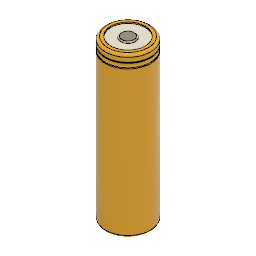
Desktop Assembly (Autodesk Fusion 360 archive; units mm, degrees)
design "18650 Battery"
Autodesk Fusion 360 part; units mm, degrees
sketch "Sketch1" plane through (0, 0, 0) normal (0, 0, 1) x (1, 0, 0)
  line L0 (0, 0) -> (0, 64.9)
  line L1 (0, 64.9) -> (9.215, 64.9)
  line L2 (9.215, 0) -> (0, 0)
  line L3 (9.215, 64.9) -> (9.215, 61.9)
  arc A0 (9.215, 61.9) -> (9.215, 60.0196) centre (10.9802, 60.9598) ccw
  line L4 (9.215, 60.0196) -> (9.215, 0)
  dimension "d1" = 9.215
  dimension "d2" = 64.9
  dimension "d5" = 2
  dimension "d6" = 3
  measures "d1" distance of L0.start
  measures "d5" radius of A0
revolve "Revolve1" add sketch "Sketch1" angle 360 about axis through (0, 0, 0) along (0, 1, 0)
fillet "Fillet1" radius 1 2 edges at (-8.5914, 64.9, -3.3323) (-8.5914, 0, -3.3323)
fillet "Fillet2" radius 1 2 edges at (-8.5914, 61.9, -3.3323) (-8.5914, 60.0196, -3.3323)
sketch "Sketch2" plane through (0, 64.9, 0) normal (0, 1, 0) x (-1, 0, 0)
  circle A0 centre (0, 0) radius 8.215
  circle A1 centre (0, 0) radius 7
  circle A2 centre (0, 0) radius 3
  dimension "d9" = 14
  dimension "d10" = 6
  measures "d9" diameter of A1
  measures "d10" diameter of A2
extrude "Extrude1" cut sketch "Sketch2" against normal blind 0.5 contours A1
fillet "Fillet3" radius 0.5 1 edges at (2.797, 64.9, -1.0848)
sketch "Sketch3" plane through (0, 0, 0) normal (0, -1, 0) x (1, 0, 0)
  circle A0 centre (0, 0) radius 8.215
  circle A1 centre (0, 0) radius 6.5
  dimension "d14" = 13
  measures "d14" diameter of A1
extrude "Extrude2" cut sketch "Sketch3" against normal blind 0.5 contours A1
equation "d1 = ( 18.43 / 2 ) * 1 mm"
